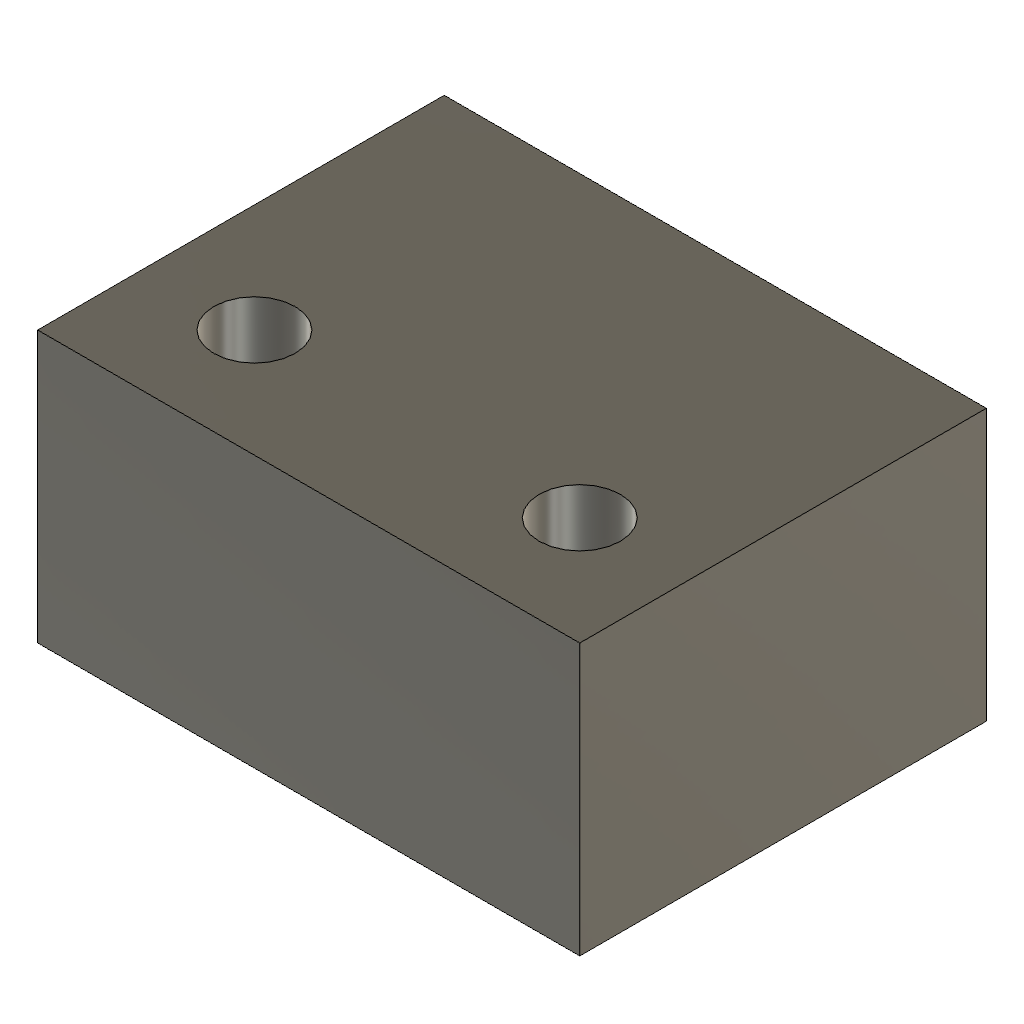
MirrorFeature (Autodesk Fusion 360 design; units mm, degrees)
part number: 2026-11-12-11-46-38-636
Autodesk Fusion 360 part; units mm, degrees
sketch "Base sketch" plane through (0, 0, 0) normal (0, 0, 1) x (1, 0, 0)
  line L0 (0, 0) -> (40, 0)
  line L1 (40, 0) -> (40, 30)
  line L2 (40, 30) -> (0, 30)
  line L3 (0, 30) -> (0, 0)
extrude "Base extrude" add sketch "Base sketch" along normal blind 20
sketch "Pocket sketch" plane through (0, 0, 0) normal (0, 0, 1) x (1, 0, 0)
  circle A0 centre (8, 8) radius 3
extrude "Pocket extrude" cut sketch "Pocket sketch" along normal blind 20
ref_plane "WorkPlane1" through (20, 0, 0) normal (1, 0, 0) x (0, 1, 0)
mirror "Pocket mirror" about plane through (20, 0, 0) normal (1, 0, 0) of "Pocket extrude"
